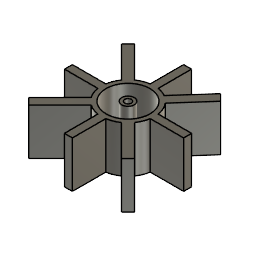
distrubutore_MEDIKITz_v2 (Autodesk Fusion 360 design; units mm, degrees)
Autodesk Fusion 360 part; units mm, degrees
sketch "Schizzo1" plane through (0, 0, 0) normal (0, 0, 1) x (1, 0, 0)
  circle A0 centre (0, 0) radius 2.5
  circle A1 centre (0, 0) radius 0.5
  line L0 (-45, 3) -> (-45, -3)
  line L1 (45, -3) -> (45, -3)
  line L2 (45, -3) -> (45, 3)
  line L3 (45, 3) -> (45, 3)
  line L4 (45, 3) -> (45, -3)
  line L5 (45, 3) -> (45, -3)
  line L6 (-3, 45) -> (3, 45)
  line L7 (-3, 19.7737) -> (-3, 45)
  line L8 (3, -45) -> (-3, -45)
  line L9 (3, -19.7737) -> (3, -45)
  line L10 (30, 40) -> (35, 35)
  line L11 (30, 40) -> (9.942, 17.3539)
  line L12 (40, -35) -> (35, -40)
  line L13 (35, -40) -> (11.4194, -16.4194)
  line L14 (40, -35) -> (16.4194, -11.4194)
  line L15 (-35, -40) -> (-40, -35)
  line L16 (-40, -35) -> (-16.4194, -11.4194)
  line L17 (-35, -40) -> (-11.4194, -16.4194)
  line L18 (-40, 35) -> (-35, 40)
  line L19 (-35, 40) -> (-11.4194, 16.4194)
  line L20 (-40, 35) -> (-16.4194, 11.4194)
  arc A2 (-16.4194, 11.4194) -> (-19.7737, 3) centre (0, 0) ccw
  arc A3 (-3, 19.7737) -> (-11.4194, 16.4194) centre (0, 0) ccw
  line L21 (3, 45) -> (3, 19.7737)
  arc A4 (9.942, 17.3539) -> (3, 19.7737) centre (0, 0) ccw
  line L22 (35, 35) -> (15.3528, 12.8177)
  line L23 (-19.7737, 3) -> (-45, 3)
  line L24 (19.7737, 3) -> (45, 3)
  arc A5 (19.7737, 3) -> (15.3528, 12.8177) centre (0, 0) ccw
  line L25 (45, -3) -> (19.7737, -3)
  line L26 (-3, -45) -> (-3, -19.7737)
  line L27 (-45, -3) -> (-19.7737, -3)
  arc A6 (-19.7737, -3) -> (-16.4194, -11.4194) centre (0, 0) ccw
  arc A7 (-11.4194, -16.4194) -> (-3, -19.7737) centre (0, 0) ccw
  arc A8 (3, -19.7737) -> (11.4194, -16.4194) centre (0, 0) ccw
  arc A9 (16.4194, -11.4194) -> (19.7737, -3) centre (0, 0) ccw
  dimension "d1" = 5
  dimension "d2" = 1
  dimension "d3" = 40
  constraint coincident A0.centre A1.centre
  constraint concentric A0 A6
  constraint horizontal L27
  constraint vertical L0
  constraint vertical L2
  constraint vertical L4
  constraint vertical L5
  constraint horizontal L25
  constraint horizontal L6
  constraint vertical L21
  constraint vertical L7
  constraint horizontal L8
  constraint vertical L26
  constraint vertical L9
  constraint parallel L11 L22
  constraint perpendicular L12 L13
  constraint perpendicular L12 L14
  constraint perpendicular L15 L16
  constraint perpendicular L15 L17
  constraint perpendicular L18 L19
  constraint perpendicular L18 L20
  constraint concentric A2 A6
  constraint concentric A3 A4
  constraint concentric A4 A5
  constraint concentric A5 A9
  constraint concentric A6 A7
  constraint concentric A7 A8
  constraint concentric A8 A9
  measures "d1" diameter of A0
  measures "d2" diameter of A1
  measures "d3" diameter of A6
extrude "Estrusione1" add sketch "Schizzo1" along normal blind 35 contours L0 L2 L4 L5 L6 L7 L8 L9 L10 L11 L12 L13 L14 L15 L16 L17 L18 L19 L20 A2 A3 L21 A4 L22 L23 L24 A5 L25 L26 L27 A6 A7 A8 A9
sketch "Schizzo2" plane through (0, 0, 35) normal (0, 0, 1) x (-1, 0, 0)
  circle A0 centre (0, 0) radius 2.5
  line L0 (-40, 35) -> (-16.4194, 11.4194)
  arc A1 (-16.4194, 11.4194) -> (-19.7737, 3) centre (0, 0) ccw
  line L1 (-19.7737, 3) -> (-45, 3)
  line L2 (-45, 3) -> (-45, -3)
  line L3 (-45, -3) -> (-19.7737, -3)
  arc A2 (-19.7737, -3) -> (-15.3528, -12.8177) centre (0, 0) ccw
  line L4 (-15.3528, -12.8177) -> (-35, -35)
  line L5 (-35, -35) -> (-30, -40)
  line L6 (-30, -40) -> (-9.942, -17.3539)
  arc A3 (-9.942, -17.3539) -> (-3, -19.7737) centre (0, 0) ccw
  line L7 (-3, -19.7737) -> (-3, -45)
  line L8 (-3, -45) -> (3, -45)
  line L9 (3, -45) -> (3, -19.7737)
  arc A4 (3, -19.7737) -> (11.4194, -16.4194) centre (0, 0) ccw
  line L10 (11.4194, -16.4194) -> (35, -40)
  line L11 (35, -40) -> (40, -35)
  line L12 (40, -35) -> (16.4194, -11.4194)
  arc A5 (16.4194, -11.4194) -> (19.7737, -3) centre (0, 0) ccw
  line L13 (19.7737, -3) -> (45, -3)
  line L14 (45, -3) -> (45, 3)
  line L15 (45, 3) -> (19.7737, 3)
  arc A6 (19.7737, 3) -> (16.4194, 11.4194) centre (0, 0) ccw
  line L16 (16.4194, 11.4194) -> (40, 35)
  line L17 (40, 35) -> (35, 40)
  line L18 (35, 40) -> (11.4194, 16.4194)
  arc A7 (11.4194, 16.4194) -> (3, 19.7737) centre (0, 0) ccw
  line L19 (3, 19.7737) -> (3, 45)
  line L20 (3, 45) -> (-3, 45)
  line L21 (-3, 45) -> (-3, 19.7737)
  arc A8 (-3, 19.7737) -> (-11.4194, 16.4194) centre (0, 0) ccw
  line L22 (-11.4194, 16.4194) -> (-35, 40)
  line L23 (-35, 40) -> (-40, 35)
  circle A9 centre (0, 0) radius 2.5
  circle A10 centre (0, 0) radius 0.5
  dimension "d6" = 1
  constraint coincident A0.centre A1.centre
  constraint concentric A0 A10
  measures "d6" diameter of A10
extrude "Estrusione2" add sketch "Schizzo2" against normal blind 24 contours A0 A9
sketch "Schizzo3" plane through (0, 0, 35) normal (0, 0, 1) x (-1, 0, 0)
  circle A0 centre (0, 0) radius 0.5
  line L0 (-40, 35) -> (-16.4194, 11.4194)
  arc A1 (-16.4194, 11.4194) -> (-19.7737, 3) centre (0, 0) ccw
  line L1 (-19.7737, 3) -> (-45, 3)
  line L2 (-45, 3) -> (-45, -3)
  line L3 (-45, -3) -> (-19.7737, -3)
  arc A2 (-19.7737, -3) -> (-15.3528, -12.8177) centre (0, 0) ccw
  line L4 (-15.3528, -12.8177) -> (-35, -35)
  line L5 (-35, -35) -> (-30, -40)
  line L6 (-30, -40) -> (-9.942, -17.3539)
  arc A3 (-9.942, -17.3539) -> (-3, -19.7737) centre (0, 0) ccw
  line L7 (-3, -19.7737) -> (-3, -45)
  line L8 (-3, -45) -> (3, -45)
  line L9 (3, -45) -> (3, -19.7737)
  arc A4 (3, -19.7737) -> (11.4194, -16.4194) centre (0, 0) ccw
  line L10 (11.4194, -16.4194) -> (35, -40)
  line L11 (35, -40) -> (40, -35)
  line L12 (40, -35) -> (16.4194, -11.4194)
  arc A5 (16.4194, -11.4194) -> (19.7737, -3) centre (0, 0) ccw
  line L13 (19.7737, -3) -> (45, -3)
  line L14 (45, -3) -> (45, 3)
  line L15 (45, 3) -> (19.7737, 3)
  arc A6 (19.7737, 3) -> (16.4194, 11.4194) centre (0, 0) ccw
  line L16 (16.4194, 11.4194) -> (40, 35)
  line L17 (40, 35) -> (35, 40)
  line L18 (35, 40) -> (11.4194, 16.4194)
  arc A7 (11.4194, 16.4194) -> (3, 19.7737) centre (0, 0) ccw
  line L19 (3, 19.7737) -> (3, 45)
  line L20 (3, 45) -> (-3, 45)
  line L21 (-3, 45) -> (-3, 19.7737)
  arc A8 (-3, 19.7737) -> (-11.4194, 16.4194) centre (0, 0) ccw
  line L22 (-11.4194, 16.4194) -> (-35, 40)
  line L23 (-35, 40) -> (-40, 35)
  circle A9 centre (0, 0) radius 2.5
  dimension "d9" = 5
  constraint concentric A0 A9
  measures "d9" diameter of A9
extrude "Estrusione3" cut sketch "Schizzo3" against normal blind 18 contours A9
sketch "Schizzo4" plane through (0, 0, 17) normal (0, 0, 1) x (-1, 0, 0)
  circle A0 centre (0, 0) radius 0.5
  circle A1 centre (0, 0) radius 2.5
  circle A2 centre (0, 0) radius 1
  constraint coincident A0.centre A1.centre
extrude "Estrusione4" cut sketch "Schizzo4" against normal blind 29 contours A2
sketch "Schizzo5" plane through (0, 0, 35) normal (0, 0, 1) x (-1, 0, 0)
  circle A0 centre (0, 0) radius 2.5
  line L0 (-40, 35) -> (-16.4194, 11.4194)
  arc A1 (-16.4194, 11.4194) -> (-19.7737, 3) centre (0, 0) ccw
  line L1 (-19.7737, 3) -> (-45, 3)
  line L2 (-45, 3) -> (-45, -3)
  line L3 (-45, -3) -> (-19.7737, -3)
  arc A2 (-19.7737, -3) -> (-15.3528, -12.8177) centre (0, 0) ccw
  line L4 (-15.3528, -12.8177) -> (-35, -35)
  line L5 (-35, -35) -> (-30, -40)
  line L6 (-30, -40) -> (-9.942, -17.3539)
  arc A3 (-9.942, -17.3539) -> (-3, -19.7737) centre (0, 0) ccw
  line L7 (-3, -19.7737) -> (-3, -45)
  line L8 (-3, -45) -> (3, -45)
  line L9 (3, -45) -> (3, -19.7737)
  arc A4 (3, -19.7737) -> (11.4194, -16.4194) centre (0, 0) ccw
  line L10 (11.4194, -16.4194) -> (35, -40)
  line L11 (35, -40) -> (40, -35)
  line L12 (40, -35) -> (16.4194, -11.4194)
  arc A5 (16.4194, -11.4194) -> (19.7737, -3) centre (0, 0) ccw
  line L13 (19.7737, -3) -> (45, -3)
  line L14 (45, -3) -> (45, 3)
  line L15 (45, 3) -> (19.7737, 3)
  arc A6 (19.7737, 3) -> (16.4194, 11.4194) centre (0, 0) ccw
  line L16 (16.4194, 11.4194) -> (40, 35)
  line L17 (40, 35) -> (35, 40)
  line L18 (35, 40) -> (11.4194, 16.4194)
  arc A7 (11.4194, 16.4194) -> (3, 19.7737) centre (0, 0) ccw
  line L19 (3, 19.7737) -> (3, 45)
  line L20 (3, 45) -> (-3, 45)
  line L21 (-3, 45) -> (-3, 19.7737)
  arc A8 (-3, 19.7737) -> (-11.4194, 16.4194) centre (0, 0) ccw
  line L22 (-11.4194, 16.4194) -> (-35, 40)
  line L23 (-35, 40) -> (-40, 35)
  circle A9 centre (0, 0) radius 16.5701
  circle A10 centre (0, 0) radius 4.771
  constraint concentric A0 A9
  constraint concentric A9 A10
extrude "Estrusione5" cut sketch "Schizzo5" against normal blind 30 contours A9
